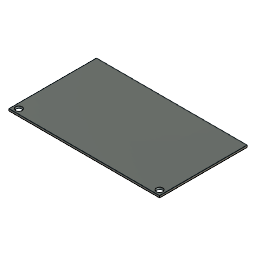
Buttons mount cover (Autodesk Fusion 360 design; units mm, degrees)
Autodesk Fusion 360 part; units mm, degrees
sketch "Sketch1" plane through (0, 0, 0) normal (0, 0, 1) x (1, 0, 0)
  line L0 (0, 0) -> (75, 0)
  line L1 (75, 0) -> (75, 43.625)
  line L2 (75, 43.625) -> (0, 43.625)
  line L3 (0, 43.625) -> (0, 0)
  dimension "d1" = 75
  dimension "d2" = 43.625
  constraint horizontal L0
  constraint vertical L1
  constraint horizontal L2
  constraint vertical L3
  constraint coincident L0.start L3.end
  measures "d1" distance of L0.start L0.end
  measures "d2" distance of L0.start L2.end
extrude "Extrude1" add sketch "Sketch1" along normal blind 1
sketch "Sketch2" plane through (0, 0, 1) normal (0, 0, 1) x (-1, 0, 0)
  line L0 (0, -43.625) -> (0, 0)
  line L1 (0, 0) -> (-75, 0)
  line L2 (-75, 0) -> (-75, -43.625)
  line L3 (-75, -43.625) -> (0, -43.625)
sketch "Sketch3" plane through (0, 0, 1) normal (0, 0, 1) x (-1, 0, 0)
  line L0 (0, -2.5) -> (-2.5, -2.5)
  line L1 (-2.5, -2.5) -> (-72.5, -2.5)
  circle A0 centre (-2.5, -2.5) radius 1.6
  circle A1 centre (-72.5, -2.5) radius 1.6
  dimension "d8" = 2.5
  dimension "d9" = 70
  dimension "d10" = 3.2
  dimension "d11" = 3.2
  constraint horizontal L0
  constraint parallel L0 L1
  constraint coincident L0.end L1.start
  constraint coincident L1.end A1.centre
  measures "d8" distance of L0.start L0.end
  measures "d9" distance of L0.end L1.end
  measures "d10" diameter of A0
  measures "d11" diameter of A1
extrude "Extrude2" cut sketch "Sketch3" against normal blind 1
